Autodesk Fusion 360 part; units mm, degrees
(part 10 of 18)
  line L7212 (85.0332, -136.031) -> (85.0347, -135.871)
  line L7213 (101.229, -141.639) -> (101.57, -141.153)
  line L7214 (169.127, -136.25) -> (169.125, -136.424)
  line L7215 (55.0587, -143.805) -> (54.5607, -144.111)
  line L7216 (155.268, -128.584) -> (155.772, -128.289)
  line L7217 (153.657, -142.493) -> (154.085, -142.905)
  line L7218 (167.879, -140.646) -> (168.153, -140.119)
  line L7219 (58.8266, -133.938) -> (58.9575, -134.508)
  line L7220 (91.5484, -127.659) -> (90.9847, -127.846)
  line L7221 (101.483, -131.217) -> (101.133, -130.737)
  line L7222 (156.578, -144.493) -> (157.132, -144.707)
  line L7223 (103.021, -136.687) -> (103.032, -136.25)
  line L7224 (154.32, -129.267) -> (154.783, -128.91)
  line L7225 (164.044, -144.384) -> (163.511, -144.623)
  line L7226 (107.909, -37.7791) -> (107.683, -38.3285)
  line L7227 (94.483, -127.304) -> (93.8893, -127.297)
  line L7228 (41.1589, -134.71) -> (41.2769, -134.137)
  line L7229 (155.518, -143.958) -> (156.039, -144.243)
  line L7230 (162.963, -144.727) -> (163.518, -144.517)
  line L7231 (155.772, -128.289) -> (156.295, -128.028)
  line L7232 (86.17, -132.046) -> (85.9088, -132.579)
  line L7233 (153.157, -130.566) -> (152.795, -131.037)
  line L7234 (153.351, -142.306) -> (152.975, -141.859)
  line L7235 (59.1268, -136.25) -> (59.1251, -136.424)
  line L7236 (87.2572, -142.054) -> (87.6569, -142.493)
  line L7237 (151.131, -137.619) -> (151.061, -137.039)
  line L7238 (85.0291, -136.455) -> (85.0332, -136.031)
  line L7239 (89.0175, -143.639) -> (89.5183, -143.958)
  line L7240 (168.602, -139.286) -> (168.389, -139.83)
  line L7241 (59.1251, -136.424) -> (59.0951, -137.007)
  line L7242 (151.382, -138.76) -> (151.238, -138.193)
  line L7243 (90.9847, -127.846) -> (90.4345, -128.069)
  line L7244 (85.2321, -134.849) -> (85.1587, -135.438)
  line L7245 (85.0347, -135.871) -> (85.078, -135.288)
  line L7246 (154.187, -143.121) -> (153.756, -142.727)
  line L7247 (166.453, -142.538) -> (166.856, -142.101)
  line L7248 (98.5813, -143.99) -> (99.0844, -143.674)
  line L7249 (97.3734, -127.924) -> (96.8143, -127.724)
  line L7250 (102.953, -135.066) -> (102.855, -134.48)
  line L7251 (165.059, -143.805) -> (164.561, -144.111)
  line L7252 (169.021, -136.687) -> (169.032, -136.25)
  line L7253 (57.3045, -130.804) -> (57.6409, -131.281)
  line L7254 (90.4345, -128.069) -> (89.9003, -128.329)
  line L7255 (152.17, -132.046) -> (151.909, -132.579)
  line L7256 (55.2028, -128.792) -> (55.6734, -129.138)
  line L7257 (152.795, -131.037) -> (152.466, -131.531)
  line L7258 (168.972, -137.279) -> (169.021, -136.687)
  line L7259 (164.059, -144.271) -> (164.581, -143.99)
  line L7260 (55.5358, -143.468) -> (55.0587, -143.805)
  line L7261 (151.078, -135.288) -> (151.159, -134.71)
  line L7262 (167.641, -131.281) -> (167.946, -131.78)
  line L7263 (169.108, -135.666) -> (169.127, -136.25)
  line L7264 (48.9269, -145.227) -> (48.35, -145.134)
  line L7265 (168.885, -137.867) -> (168.972, -137.279)
  line L7266 (156.039, -144.243) -> (156.578, -144.493)
  line L7267 (108.795, -36.2371) -> (108.466, -36.7311)
  line L7268 (153.257, -142.054) -> (153.657, -142.493)
  line L7269 (85.9741, -140.063) -> (86.2446, -140.591)
  line L7270 (45.7724, -128.289) -> (46.2951, -128.028)
  line L7271 (52.4039, -144.996) -> (51.8346, -145.128)
  line L7272 (152.888, -141.589) -> (153.257, -142.054)
  line L7273 (96.8143, -127.724) -> (96.2432, -127.561)
  line L7274 (167.199, -141.834) -> (166.823, -142.282)
  line L7275 (51.2581, -145.223) -> (50.6766, -145.28)
  line L7276 (151.683, -133.129) -> (151.495, -133.692)
  line L7277 (85.1245, -136.031) -> (85.1297, -136.625)
  line L7278 (108.466, -36.7311) -> (108.17, -37.2459)
  line L7279 (102.719, -133.902) -> (102.544, -133.335)
  line L7280 (41.8482, -132.483) -> (42.1085, -131.96)
  line L7281 (103.012, -135.657) -> (102.953, -135.066)
  line L7282 (107.683, -38.3285) -> (107.495, -38.8917)
  line L7283 (164.199, -128.194) -> (164.711, -128.476)
  line L7284 (152.311, -140.898) -> (152.028, -140.387)
  line L7285 (152.975, -141.859) -> (152.627, -141.389)
  line L7286 (166.543, -129.918) -> (166.938, -130.349)
  line L7287 (98.0585, -144.271) -> (98.5813, -143.99)
  line L7288 (102.885, -137.867) -> (102.972, -137.279)
  line L7289 (107.13, -41.825) -> (107.174, -42.4171)
  line L7290 (163.128, -127.73) -> (163.671, -127.944)
  line L7291 (86.5495, -141.101) -> (86.8876, -141.589)
  line L7292 (53.671, -127.944) -> (54.1995, -128.194)
  line L7293 (151.541, -138.958) -> (151.739, -139.517)
  line L7294 (151.232, -134.849) -> (151.159, -135.438)
  line L7295 (151.124, -136.031) -> (151.13, -136.625)
  line L7296 (168.855, -134.48) -> (168.719, -133.902)
  line L7297 (160.483, -127.304) -> (159.889, -127.297)
  line L7298 (151.777, -139.859) -> (151.562, -139.316)
  line L7299 (85.7774, -139.859) -> (85.5618, -139.316)
  line L7300 (161.816, -145.034) -> (162.395, -144.9)
  line L7301 (89.9003, -128.329) -> (89.3845, -128.623)
  line L7302 (168.659, -133.378) -> (168.827, -133.938)
  line L7303 (85.3803, -138.386) -> (85.541, -138.958)
  line L7304 (101.801, -131.718) -> (101.483, -131.217)
  line L7305 (169.032, -136.25) -> (169.012, -135.657)
  line L7306 (85.2578, -137.805) -> (85.3803, -138.386)
  line L7307 (100.453, -142.538) -> (100.856, -142.101)
  line L7308 (151.739, -139.517) -> (151.974, -140.063)
  line L7309 (87.5489, -130.12) -> (87.157, -130.566)
  line L7310 (165.565, -143.326) -> (166.022, -142.947)
  line L7311 (167.57, -141.153) -> (167.879, -140.646)
  line L7312 (151.277, -134.137) -> (151.432, -133.574)
  line L7313 (102.972, -137.279) -> (103.021, -136.687)
  line L7314 (51.4301, -127.302) -> (52.0047, -127.408)
  line L7315 (58.4559, -132.831) -> (58.6591, -133.378)
  line L7316 (55.6734, -129.138) -> (56.1207, -129.514)
  line L7317 (166.753, -130.281) -> (166.342, -129.852)
  line L7318 (154.889, -128.951) -> (154.417, -129.31)
  line L7319 (57.5441, -141.363) -> (57.1986, -141.834)
  line L7320 (85.7392, -139.517) -> (85.9741, -140.063)
  line L7321 (151.035, -135.871) -> (151.078, -135.288)
  line L7322 (157.22, -144.837) -> (156.672, -144.635)
  line L7323 (95.075, -127.351) -> (94.483, -127.304)
  line L7324 (163.511, -144.623) -> (162.963, -144.827)
  line L7325 (54.1995, -128.194) -> (54.7108, -128.476)
  line L7326 (86.6274, -141.389) -> (86.3113, -140.898)
  line L7327 (59.0951, -137.007) -> (59.0274, -137.588)
  line L7328 (99.4411, -129.079) -> (98.954, -128.74)
  line L7329 (151.622, -133.022) -> (151.848, -132.483)
  line L7330 (169.051, -135.084) -> (169.108, -135.666)
  line L7331 (102.391, -139.576) -> (102.594, -139.017)
  line L7332 (159.099, -127.253) -> (159.682, -127.209)
  line L7333 (161.663, -127.437) -> (161.075, -127.351)
  line L7334 (56.1207, -129.514) -> (56.5428, -129.918)
  line L7335 (168.389, -139.83) -> (168.14, -140.359)
  line L7336 (50.8498, -127.233) -> (51.4301, -127.302)
  line L7337 (45.2676, -128.584) -> (45.7724, -128.289)
  line L7338 (53.5109, -144.623) -> (52.9634, -144.827)
  line L7339 (85.1309, -137.619) -> (85.0612, -137.039)
  line L7340 (151.344, -134.266) -> (151.232, -134.849)
  line L7341 (169.027, -137.588) -> (168.922, -138.162)
  line L7342 (163.373, -127.924) -> (162.814, -127.724)
  line L7343 (159.889, -127.297) -> (159.296, -127.329)
  line L7344 (46.8336, -127.801) -> (47.3856, -127.609)
  line L7345 (161.258, -145.223) -> (160.677, -145.28)
  line L7346 (94.6391, -145.187) -> (95.2302, -145.13)
  line L7347 (85.541, -138.958) -> (85.7392, -139.517)
  line L7348 (42.7274, -130.969) -> (43.0836, -130.506)
  line L7349 (88.0847, -142.905) -> (88.539, -143.287)
  line L7350 (107.159, -40.6384) -> (107.124, -41.2312)
  line L7351 (159.682, -127.209) -> (160.266, -127.202)
  line L7352 (55.9903, -143.101) -> (55.5358, -143.468)
  line L7353 (167.133, -130.737) -> (166.753, -130.281)
  line L7354 (85.3817, -138.76) -> (85.2379, -138.193)
  line L7355 (153.97, -129.701) -> (153.549, -130.12)
  line L7356 (41.078, -135.288) -> (41.1589, -134.71)
  line L7357 (155.9, -128.329) -> (155.385, -128.623)
  line L7358 (153.549, -130.12) -> (153.157, -130.566)
  line L7359 (86.0276, -140.387) -> (85.7774, -139.859)
  line L7360 (159.296, -127.329) -> (158.707, -127.4)
  line L7361 (52.0047, -127.408) -> (52.5713, -127.551)
  line L7362 (156.672, -144.635) -> (156.138, -144.398)
  line L7363 (164.711, -128.476) -> (165.203, -128.792)
  line L7364 (154.643, -143.487) -> (154.187, -143.121)
  line L7365 (109.157, -35.766) -> (108.795, -36.2371)
  line L7366 (49.5085, -145.282) -> (48.9269, -145.227)
  line L7367 (101.133, -130.737) -> (100.753, -130.281)
  line L7368 (95.6626, -127.437) -> (95.075, -127.351)
  line L7369 (153.084, -130.506) -> (153.469, -130.066)
  line L7370 (102.084, -132.24) -> (101.801, -131.718)
  line L7371 (165.904, -129.451) -> (165.441, -129.079)
  line L7372 (86.9746, -141.859) -> (86.6274, -141.389)
  line L7373 (168.14, -140.359) -> (167.858, -140.87)
  line L7374 (88.539, -143.287) -> (89.0175, -143.639)
  line L7375 (154.783, -128.91) -> (155.268, -128.584)
  line L7376 (168.084, -132.24) -> (167.801, -131.718)
  line L7377 (164.954, -128.74) -> (164.446, -128.433)
  line L7378 (165.536, -143.468) -> (165.059, -143.805)
  line L7379 (165.441, -129.079) -> (164.954, -128.74)
  line L7380 (50.2663, -127.202) -> (50.8498, -127.233)
  line L7381 (109.97, -34.9007) -> (109.549, -35.3199)
  line L7382 (91.1318, -144.707) -> (91.6987, -144.883)
  line L7383 (152.55, -141.101) -> (152.888, -141.589)
  line L7384 (57.9457, -131.78) -> (58.2178, -132.297)
  line L7385 (58.1404, -140.359) -> (57.8585, -140.87)
  line L7386 (99.5654, -143.326) -> (100.022, -142.947)
  line L7387 (156.138, -144.398) -> (155.62, -144.127)
  line L7388 (96.3945, -144.9) -> (96.9627, -144.727)
  line L7389 (101.879, -140.646) -> (102.153, -140.119)
  line L7390 (158.707, -127.4) -> (158.123, -127.511)
  line L7391 (153.469, -130.066) -> (153.882, -129.653)
  line L7392 (151.159, -134.71) -> (151.277, -134.137)
  line L7393 (151.238, -138.193) -> (151.131, -137.619)
  line L7394 (44.3203, -129.267) -> (44.7829, -128.91)
  line L7395 (164.581, -143.99) -> (165.084, -143.674)
  line L7396 (50.6766, -145.28) -> (50.0926, -145.3)
  line L7397 (85.495, -133.692) -> (85.3443, -134.266)
  line L7398 (43.0836, -130.506) -> (43.4688, -130.066)
  line L7399 (168.153, -140.119) -> (168.391, -139.576)
  line L7400 (52.5713, -127.551) -> (53.1275, -127.73)
  line L7401 (52.9634, -144.827) -> (52.4039, -144.996)
  line L7402 (162.005, -127.408) -> (162.571, -127.551)
  line L7403 (159.509, -145.282) -> (158.927, -145.227)
  line L7404 (162.571, -127.551) -> (163.128, -127.73)
  line L7405 (159.452, -145.183) -> (160.046, -145.205)
  line L7406 (43.4688, -130.066) -> (43.8816, -129.653)
  line L7407 (167.483, -131.217) -> (167.133, -130.737)
  line L7408 (160.639, -145.187) -> (161.23, -145.13)
  line L7409 (93.4521, -145.183) -> (94.0455, -145.205)
  line L7410 (160.85, -127.233) -> (161.43, -127.302)
  line L7411 (87.157, -130.566) -> (86.7955, -131.037)
  line L7412 (168.758, -138.447) -> (168.885, -137.867)
  line L7413 (54.0441, -144.384) -> (53.5109, -144.623)
  line L7414 (99.9045, -129.451) -> (99.4411, -129.079)
  line L7415 (168.456, -132.831) -> (168.659, -133.378)
  line L7416 (166.121, -129.514) -> (166.543, -129.918)
  line L7417 (50.0926, -145.3) -> (49.5085, -145.282)
  line L7418 (157.132, -144.707) -> (157.699, -144.883)
  line L7419 (151.13, -136.625) -> (151.174, -137.217)
  line L7420 (95.2302, -145.13) -> (95.8162, -145.034)
  line L7421 (43.8816, -129.653) -> (44.3203, -129.267)
  line L7422 (56.9379, -130.349) -> (57.3045, -130.804)
  line L7423 (165.673, -129.138) -> (166.121, -129.514)
  line L7424 (161.075, -127.351) -> (160.483, -127.304)
  line L7425 (56.5428, -129.918) -> (56.9379, -130.349)
  line L7426 (56.8234, -142.282) -> (56.42, -142.705)
  line L7427 (167.544, -141.363) -> (167.199, -141.834)
  line L7428 (167.801, -131.718) -> (167.483, -131.217)
  line L7429 (48.35, -145.134) -> (47.7803, -145.004)
  line L7430 (101.57, -141.153) -> (101.879, -140.646)
  line L7431 (168.719, -133.902) -> (168.544, -133.335)
  line L7432 (168.953, -135.066) -> (168.855, -134.48)
  line L7433 (151.033, -136.031) -> (151.035, -135.871)
  line L7434 (166.823, -142.282) -> (166.42, -142.705)
  line L7435 (49.682, -127.209) -> (50.2663, -127.202)
  line L7436 (152.627, -141.389) -> (152.311, -140.898)
  line L7437 (59.1079, -135.666) -> (59.1268, -136.25)
  line L7438 (151.061, -137.039) -> (151.029, -136.455)
  line L7439 (85.1587, -135.438) -> (85.1245, -136.031)
  line L7440 (164.561, -144.111) -> (164.044, -144.384)
  line L7441 (153.756, -142.727) -> (153.351, -142.306)
  line L7442 (158.123, -127.511) -> (157.548, -127.659)
  line L7443 (168.781, -138.729) -> (168.602, -139.286)
  line L7444 (160.677, -145.28) -> (160.093, -145.3)
  line L7445 (167.304, -130.804) -> (167.641, -131.281)
  line L7446 (156.834, -127.801) -> (157.386, -127.609)
  line L7447 (158.927, -145.227) -> (158.35, -145.134)
  line L7448 (157.78, -145.004) -> (157.22, -144.837)
  line L7449 (47.7803, -145.004) -> (47.2202, -144.837)
  line L7450 (46.2951, -128.028) -> (46.8336, -127.801)
  line L7451 (156.434, -128.069) -> (155.9, -128.329)
  line L7452 (157.949, -127.454) -> (158.521, -127.335)
  line L7453 (168.957, -134.508) -> (169.051, -135.084)
  line L7454 (152.108, -131.96) -> (152.402, -131.454)
  line L7455 (167.946, -131.78) -> (168.218, -132.297)
  line L7456 (47.9488, -127.454) -> (48.5208, -127.335)
  line L7457 (151.909, -132.579) -> (151.683, -133.129)
  line L7458 (169.095, -137.007) -> (169.027, -137.588)
  line L7459 (157.548, -127.659) -> (156.985, -127.846)
  line L7460 (102.332, -132.78) -> (102.084, -132.24)
  line L7461 (97.9179, -128.161) -> (97.3734, -127.924)
  line L7462 (157.386, -127.609) -> (157.949, -127.454)
  line L7463 (168.391, -139.576) -> (168.594, -139.017)
  line L7464 (168.218, -132.297) -> (168.456, -132.831)
  line L7465 (156.295, -128.028) -> (156.834, -127.801)
  line L7466 (47.3856, -127.609) -> (47.9488, -127.454)
  line L7467 (125.012, -40.8565) -> (124.953, -40.2656)
  line L7468 (113.548, -32.8593) -> (112.985, -33.0458)
  line L7469 (122.342, -35.0519) -> (121.904, -34.6507)
  line L7470 (119.918, -33.3606) -> (119.373, -33.1239)
  line L7471 (122.753, -35.4812) -> (122.342, -35.0519)
  line L7472 (124.885, -43.0665) -> (124.972, -42.4793)
  line L7473 (120.581, -49.1896) -> (121.084, -48.874)
  line L7474 (122.453, -47.7378) -> (122.856, -47.3014)
  line L7475 (117.075, -32.5508) -> (116.483, -32.5042)
  line L7476 (123.133, -35.9368) -> (122.753, -35.4812)
  line L7477 (111.385, -33.8228) -> (110.889, -34.1505)
  line L7478 (121.565, -48.5258) -> (122.022, -48.1465)
  line L7479 (119.518, -49.7173) -> (120.059, -49.4711)
  line L7480 (125.021, -41.8875) -> (125.032, -41.45)
  line L7481 (116.046, -50.4049) -> (116.639, -50.3873)
  line L7482 (124.544, -38.5345) -> (124.332, -37.9798)
  line L7483 (118.963, -49.9272) -> (119.518, -49.7173)
  line L7484 (118.395, -50.0999) -> (118.963, -49.9272)
  line L7485 (121.441, -34.2794) -> (120.954, -33.9397)
  line L7486 (123.801, -36.9185) -> (123.483, -36.4165)
  line L7487 (116.639, -50.3873) -> (117.23, -50.3304)
  line L7488 (121.904, -34.6507) -> (121.441, -34.2794)
  line L7489 (111.9, -33.5286) -> (111.385, -33.8228)
  line L7490 (119.373, -33.1239) -> (118.814, -32.9237)
  line L7491 (124.953, -40.2656) -> (124.855, -39.68)
  line L7492 (113.132, -49.9069) -> (113.699, -50.0835)
  line L7493 (118.814, -32.9237) -> (118.243, -32.761)
  line L7494 (114.707, -32.6004) -> (114.123, -32.7107)
  line L7495 (114.123, -32.7107) -> (113.548, -32.8593)
  line L7496 (121.084, -48.874) -> (121.565, -48.5258)
  line L7497 (123.879, -45.846) -> (124.153, -45.3193)
  line L7498 (117.663, -32.6365) -> (117.075, -32.5508)
  line L7499 (116.483, -32.5042) -> (115.889, -32.497)
  line L7500 (115.452, -50.3832) -> (116.046, -50.4049)
  line L7501 (124.084, -37.4403) -> (123.801, -36.9185)
  line L7502 (124.972, -42.4793) -> (125.021, -41.8875)
  line L7503 (123.483, -36.4165) -> (123.133, -35.9368)
  line L7504 (120.446, -33.633) -> (119.918, -33.3606)
  line L7505 (115.889, -32.497) -> (115.296, -32.5291)
  line L7506 (122.022, -48.1465) -> (122.453, -47.7378)
  line L7507 (117.23, -50.3304) -> (117.816, -50.2345)
  line L7508 (114.276, -50.2221) -> (114.861, -50.3221)
  line L7509 (124.391, -44.7756) -> (124.594, -44.2172)
  line L7510 (110.889, -34.1505) -> (110.417, -34.5104)
  line L7511 (118.243, -32.761) -> (117.663, -32.6365)
  line L7512 (122.856, -47.3014) -> (123.229, -46.8393)
  line L7513 (124.855, -39.68) -> (124.719, -39.1021)
  line L7514 (112.985, -33.0458) -> (112.434, -33.2692)
  line L7515 (117.816, -50.2345) -> (118.395, -50.0999)
  line L7516 (112.434, -33.2692) -> (111.9, -33.5286)
  line L7517 (124.153, -45.3193) -> (124.391, -44.7756)
  line L7518 (113.699, -50.0835) -> (114.276, -50.2221)
  line L7519 (125.032, -41.45) -> (125.012, -40.8565)
  line L7520 (124.594, -44.2172) -> (124.758, -43.6467)
  line L7521 (123.57, -46.3534) -> (123.879, -45.846)
  line L7522 (115.296, -32.5291) -> (114.707, -32.6004)
  line L7523 (114.861, -50.3221) -> (115.452, -50.3832)
  line L7524 (120.954, -33.9397) -> (120.446, -33.633)
  line L7525 (124.758, -43.6467) -> (124.885, -43.0665)
  line L7526 (124.719, -39.1021) -> (124.544, -38.5345)
  line L7527 (124.332, -37.9798) -> (124.084, -37.4403)
  line L7528 (120.059, -49.4711) -> (120.581, -49.1896)
  line L7529 (123.229, -46.8393) -> (123.57, -46.3534)
  line L7530 (125.095, -42.2073) -> (125.027, -42.7877)
  line L7531 (125.027, -42.7877) -> (124.922, -43.3625)
  line L7532 (107.033, -41.2312) -> (107.035, -41.071)
  line L7533 (112.039, -49.4431) -> (112.578, -49.6931)
  line L7534 (107.238, -43.3934) -> (107.131, -42.8189)
  line L7535 (107.541, -44.1577) -> (107.739, -44.7175)
  line L7536 (107.777, -45.0587) -> (107.562, -44.5156)
  line L7537 (125.127, -41.45) -> (125.125, -41.6237)
  line L7538 (107.562, -44.5156) -> (107.382, -43.9597)
  line L7539 (121.059, -49.0054) -> (120.561, -49.3111)
  line L7540 (124.827, -39.1382) -> (124.957, -39.7077)
  line L7541 (124.14, -45.5586) -> (123.858, -46.0704)
  line L7542 (107.061, -42.2388) -> (107.029, -41.6553)
  line L7543 (124.922, -43.3625) -> (124.781, -43.9293)
  line L7544 (116.677, -50.4801) -> (116.093, -50.5)
  line L7545 (109.756, -47.927) -> (109.351, -47.5056)
  line L7546 (123.858, -46.0704) -> (123.544, -46.563)
  line L7547 (118.963, -50.0273) -> (118.404, -50.1957)
  line L7548 (117.835, -50.3276) -> (117.258, -50.4226)
  line L7549 (115.509, -50.4821) -> (114.927, -50.4266)
  line L7550 (119.511, -49.8231) -> (118.963, -50.0273)
  line L7551 (108.55, -46.301) -> (108.888, -46.7892)
  line L7552 (112.578, -49.6931) -> (113.132, -49.9069)
  line L7553 (107.131, -42.8189) -> (107.061, -42.2388)
  line L7554 (122.823, -47.4821) -> (122.42, -47.9049)
  line L7555 (108.627, -46.589) -> (108.311, -46.0975)
  line L7556 (111.62, -49.3267) -> (111.121, -49.0227)
  line L7557 (108.245, -45.7915) -> (108.55, -46.301)
  line L7558 (108.888, -46.7892) -> (109.257, -47.2539)
  line L7559 (120.044, -49.5841) -> (119.511, -49.8231)
  line L7560 (111.121, -49.0227) -> (110.643, -48.6871)
  line L7561 (109.657, -47.6931) -> (110.085, -48.1049)
  line L7562 (108.028, -45.5867) -> (107.777, -45.0587)
  line L7563 (114.35, -50.3337) -> (113.78, -50.2038)
  line L7564 (110.539, -48.4873) -> (111.018, -48.8389)
  line L7565 (111.018, -48.8389) -> (111.518, -49.1579)
  line L7566 (109.257, -47.2539) -> (109.657, -47.6931)
  line L7567 (124.659, -38.5784) -> (124.827, -39.1382)
  line L7568 (125.108, -40.866) -> (125.127, -41.45)
  line L7569 (124.389, -45.0297) -> (124.14, -45.5586)
  line L7570 (117.258, -50.4226) -> (116.677, -50.4801)
  line L7571 (110.643, -48.6871) -> (110.187, -48.3214)
  line L7572 (116.093, -50.5) -> (115.509, -50.4821)
  line L7573 (108.975, -47.059) -> (108.627, -46.589)
  line L7574 (124.456, -38.0305) -> (124.659, -38.5784)
  line L7575 (124.781, -43.9293) -> (124.602, -44.4858)
  line L7576 (107.035, -41.071) -> (107.078, -40.4883)
  line L7577 (114.927, -50.4266) -> (114.35, -50.3337)
  line L7578 (107.974, -45.2629) -> (108.245, -45.7915)
  line L7579 (111.518, -49.1579) -> (112.039, -49.4431)
  line L7580 (112.138, -49.5979) -> (111.62, -49.3267)
  line L7581 (121.99, -48.3008) -> (121.536, -48.6681)
  line L7582 (124.957, -39.7077) -> (125.051, -40.2844)
  line L7583 (107.739, -44.7175) -> (107.974, -45.2629)
  line L7584 (107.382, -43.9597) -> (107.238, -43.3934)
  line L7585 (109.351, -47.5056) -> (108.975, -47.059)
  line L7586 (123.199, -47.0342) -> (122.823, -47.4821)
  line L7587 (110.187, -48.3214) -> (109.756, -47.927)
  line L7588 (123.544, -46.563) -> (123.199, -47.0342)
  line L7589 (107.174, -42.4171) -> (107.258, -43.005)
  line L7590 (118.404, -50.1957) -> (117.835, -50.3276)
  line L7591 (120.561, -49.3111) -> (120.044, -49.5841)
  line L7592 (108.311, -46.0975) -> (108.028, -45.5867)
  line L7593 (112.672, -49.8351) -> (112.138, -49.5979)
  line L7594 (124.602, -44.4858) -> (124.389, -45.0297)
  line L7595 (113.78, -50.2038) -> (113.22, -50.0373)
  line L7596 (110.085, -48.1049) -> (110.539, -48.4873)
  line L7597 (107.029, -41.6553) -> (107.033, -41.2312)
  line L7598 (125.125, -41.6237) -> (125.095, -42.2073)
  line L7599 (107.258, -43.005) -> (107.38, -43.5861)
  line L7600 (121.536, -48.6681) -> (121.059, -49.0054)
  line L7601 (113.22, -50.0373) -> (112.672, -49.8351)
  line L7602 (122.42, -47.9049) -> (121.99, -48.3008)
  line L7603 (125.051, -40.2844) -> (125.108, -40.866)
  line L7604 (124.218, -37.4969) -> (124.456, -38.0305)
  line L7605 (107.38, -43.5861) -> (107.541, -44.1577)
  line L7606 (173.159, -40.6384) -> (173.124, -41.2312)
  line L7607 (91.3856, -32.8094) -> (91.9488, -32.6538)
  line L7608 (98.5607, -49.3111) -> (98.0441, -49.5841)
  line L7609 (174.466, -36.7311) -> (174.17, -37.2459)
  line L7610 (103.027, -42.7877) -> (102.922, -43.3625)
  line L7611 (89.6204, -49.3267) -> (89.1214, -49.0227)
  line L7612 (92.5208, -32.5348) -> (93.0994, -32.4529)
  line L7613 (85.2769, -39.3373) -> (85.4315, -38.7738)
  line L7614 (93.682, -32.4086) -> (94.2663, -32.402)
  line L7615 (102.14, -45.5586) -> (101.858, -46.0704)
  line L7616 (101.544, -46.563) -> (101.199, -47.0342)
  line L7617 (102.218, -37.4969) -> (102.456, -38.0305)
  line L7618 (101.946, -36.9798) -> (102.218, -37.4969)
  line L7619 (91.7803, -50.2038) -> (91.2202, -50.0373)
  line L7620 (99.2028, -33.9917) -> (99.6734, -34.338)
  line L7621 (101.304, -36.0036) -> (101.641, -36.4813)
  line L7622 (86.1085, -37.1595) -> (86.402, -36.6542)
  line L7623 (96.0047, -32.6077) -> (96.5713, -32.7506)
  line L7624 (86.7274, -36.169) -> (87.0836, -35.7057)
  line L7625 (89.7724, -33.4892) -> (90.2951, -33.228)
  line L7626 (103.095, -42.2073) -> (103.027, -42.7877)
  line L7627 (98.7108, -33.6764) -> (99.2028, -33.9917)
  line L7628 (91.2202, -50.0373) -> (90.672, -49.8351)
  line L7629 (103.108, -40.866) -> (103.127, -41.45)
  line L7630 (95.2581, -50.4226) -> (94.6766, -50.4801)
  line L7631 (95.8346, -50.3276) -> (95.2581, -50.4226)
  line L7632 (102.456, -38.0305) -> (102.659, -38.5784)
  line L7633 (88.7829, -34.1099) -> (89.2676, -33.7835)
  line L7634 (92.35, -50.3337) -> (91.7803, -50.2038)
  line L7635 (85.6222, -38.2215) -> (85.8482, -37.6827)
  line L7636 (94.8498, -32.4331) -> (95.4301, -32.5018)
  line L7637 (102.659, -38.5784) -> (102.827, -39.1382)
  line L7638 (100.823, -47.4821) -> (100.42, -47.9049)
  line L7639 (90.8336, -33.0011) -> (91.3856, -32.8094)
  line L7640 (97.671, -33.1443) -> (98.1995, -33.3936)
  line L7641 (89.1214, -49.0227) -> (88.643, -48.6871)
  line L7642 (98.1995, -33.3936) -> (98.7108, -33.6764)
  line L7643 (88.643, -48.6871) -> (88.1873, -48.3214)
  line L7644 (90.672, -49.8351) -> (90.138, -49.5979)
  line L7645 (94.0926, -50.5) -> (93.5085, -50.4821)
  line L7646 (173.13, -41.825) -> (173.174, -42.4171)
  line L7647 (98.0441, -49.5841) -> (97.5109, -49.8231)
  line L7648 (101.858, -46.0704) -> (101.544, -46.563)
  line L7649 (99.0587, -49.0054) -> (98.5607, -49.3111)
  line L7650 (94.6766, -50.4801) -> (94.0926, -50.5)
  line L7651 (174.17, -37.2459) -> (173.909, -37.7791)
  line L7652 (90.2951, -33.228) -> (90.8336, -33.0011)
  line L7653 (100.121, -34.714) -> (100.543, -35.118)
  line L7654 (100.42, -47.9049) -> (99.9903, -48.3008)
  line L7655 (87.4688, -35.2664) -> (87.8816, -34.8528)
  line L7656 (97.5109, -49.8231) -> (96.9634, -50.0273)
  line L7657 (99.6734, -34.338) -> (100.121, -34.714)
  line L7658 (102.602, -44.4858) -> (102.389, -45.0297)
  line L7659 (85.4315, -38.7738) -> (85.6222, -38.2215)
  line L7660 (173.495, -38.8917) -> (173.344, -39.466)
  line L7661 (102.827, -39.1382) -> (102.957, -39.7077)
  line L7662 (102.389, -45.0297) -> (102.14, -45.5586)
  line L7663 (85.078, -40.4883) -> (85.1589, -39.9096)
  line L7664 (86.402, -36.6542) -> (86.7274, -36.169)
  line L7665 (96.5713, -32.7506) -> (97.1275, -32.9297)
  line L7666 (173.344, -39.466) -> (173.232, -40.0491)
  line L7667 (97.1275, -32.9297) -> (97.671, -33.1443)
  line L7668 (173.124, -41.2312) -> (173.13, -41.825)
  line L7669 (96.9634, -50.0273) -> (96.4039, -50.1957)
  line L7670 (93.5085, -50.4821) -> (92.9269, -50.4266)
  line L7671 (89.2676, -33.7835) -> (89.7724, -33.4892)
  line L7672 (103.051, -40.2844) -> (103.108, -40.866)
  line L7673 (99.9903, -48.3008) -> (99.5358, -48.6681)
  line L7674 (95.4301, -32.5018) -> (96.0047, -32.6077)
  line L7675 (102.781, -43.9293) -> (102.602, -44.4858)
  line L7676 (101.641, -36.4813) -> (101.946, -36.9798)
  line L7677 (102.957, -39.7077) -> (103.051, -40.2844)
  line L7678 (92.9269, -50.4266) -> (92.35, -50.3337)
  line L7679 (103.125, -41.6237) -> (103.095, -42.2073)
  line L7680 (173.683, -38.3285) -> (173.495, -38.8917)
  line L7681 (101.199, -47.0342) -> (100.823, -47.4821)
  line L7682 (85.8482, -37.6827) -> (86.1085, -37.1595)
  line L7683 (99.5358, -48.6681) -> (99.0587, -49.0054)
  line L7684 (87.8816, -34.8528) -> (88.3203, -34.4668)
  line L7685 (103.127, -41.45) -> (103.125, -41.6237)
  line L7686 (87.0836, -35.7057) -> (87.4688, -35.2664)
  line L7687 (93.0994, -32.4529) -> (93.682, -32.4086)
  line L7688 (102.922, -43.3625) -> (102.781, -43.9293)
  line L7689 (91.9488, -32.6538) -> (92.5208, -32.5348)
  line L7690 (88.3203, -34.4668) -> (88.7829, -34.1099)
  line L7691 (173.232, -40.0491) -> (173.159, -40.6384)
  line L7692 (85.1589, -39.9096) -> (85.2769, -39.3373)
  line L7693 (94.2663, -32.402) -> (94.8498, -32.4331)
  line L7694 (100.543, -35.118) -> (100.938, -35.5485)
  line L7695 (96.4039, -50.1957) -> (95.8346, -50.3276)
  line L7696 (173.909, -37.7791) -> (173.683, -38.3285)
  line L7697 (90.138, -49.5979) -> (89.6204, -49.3267)
  line L7698 (100.938, -35.5485) -> (101.304, -36.0036)
  line L7699 (190.972, -42.4793) -> (191.021, -41.8875)
  line L7700 (190.855, -39.68) -> (190.719, -39.1021)
  line L7701 (189.57, -46.3534) -> (189.879, -45.846)
  line L7702 (190.544, -38.5345) -> (190.332, -37.9798)
  line L7703 (177.9, -33.5286) -> (177.385, -33.8228)
  line L7704 (191.012, -40.8565) -> (190.953, -40.2656)
  line L7705 (183.816, -50.2345) -> (184.395, -50.0999)
  line L7706 (173.382, -43.9597) -> (173.238, -43.3934)
  line L7707 (175.97, -200.801) -> (175.549, -201.22)
  line L7708 (178.985, -33.0458) -> (178.434, -33.2692)
  line L7709 (181.452, -50.3832) -> (182.046, -50.4049)
  line L7710 (190.719, -39.1021) -> (190.544, -38.5345)
  line L7711 (182.483, -32.5042) -> (181.889, -32.497)
  line L7712 (173.174, -42.4171) -> (173.258, -43.005)
  line L7713 (173.033, -41.2312) -> (173.035, -41.071)
  line L7714 (183.663, -32.6365) -> (183.075, -32.5508)
  line L7715 (173.13, -207.725) -> (173.174, -208.317)
  line L7716 (190.594, -44.2172) -> (190.758, -43.6467)
  line L7717 (181.296, -32.5291) -> (180.707, -32.6004)
  line L7718 (175.657, -47.6931) -> (176.085, -48.1049)
  line L7719 (178.434, -33.2692) -> (177.9, -33.5286)
  line L7720 (184.814, -32.9237) -> (184.243, -32.761)
  line L7721 (175.157, -201.666) -> (174.795, -202.137)
  line L7722 (173.495, -204.792) -> (173.344, -205.366)
  line L7723 (180.861, -50.3221) -> (181.452, -50.3832)
  line L7724 (183.23, -50.3304) -> (183.816, -50.2345)
  line L7725 (191.032, -41.45) -> (191.012, -40.8565)
  line L7726 (181.889, -32.497) -> (181.296, -32.5291)
  line L7727 (179.548, -32.8593) -> (178.985, -33.0458)
  line L7728 (176.539, -48.4873) -> (177.018, -48.8389)
  line L7729 (187.441, -34.2794) -> (186.954, -33.9397)
  line L7730 (189.133, -35.9368) -> (188.753, -35.4812)
  line L7731 (173.258, -43.005) -> (173.38, -43.5861)
  line L7732 (180.276, -50.2221) -> (180.861, -50.3221)
  line L7733 (174.55, -46.301) -> (174.888, -46.7892)
  line L7734 (182.046, -50.4049) -> (182.639, -50.3873)
  line L7735 (174.888, -46.7892) -> (175.257, -47.2539)
  line L7736 (63.078, -206.388) -> (63.1589, -205.81)
  line L7737 (188.022, -48.1465) -> (188.453, -47.7378)
  line L7738 (177.385, -33.8228) -> (176.889, -34.1505)
  line L7739 (174.795, -202.137) -> (174.466, -202.631)
  line L7740 (173.974, -45.2629) -> (174.245, -45.7915)
  line L7741 (173.124, -207.131) -> (173.13, -207.725)
  line L7742 (179.699, -50.0835) -> (180.276, -50.2221)
  line L7743 (173.344, -205.366) -> (173.232, -205.949)
  line L7744 (189.483, -36.4165) -> (189.133, -35.9368)
  line L7745 (173.131, -42.8189) -> (173.061, -42.2388)
  line L7746 (186.446, -33.633) -> (185.918, -33.3606)
  line L7747 (176.417, -34.5104) -> (175.97, -34.9007)
  line L7748 (173.232, -205.949) -> (173.159, -206.538)
  line L7749 (180.123, -32.7107) -> (179.548, -32.8593)
  line L7750 (173.159, -206.538) -> (173.124, -207.131)
  line L7751 (186.954, -33.9397) -> (186.446, -33.633)
  line L7752 (173.909, -203.679) -> (173.683, -204.229)
  line L7753 (188.856, -47.3014) -> (189.229, -46.8393)
  line L7754 (184.395, -50.0999) -> (184.963, -49.9272)
  line L7755 (185.518, -49.7173) -> (186.059, -49.4711)
  line L7756 (184.963, -49.9272) -> (185.518, -49.7173)
  line L7757 (174.466, -202.631) -> (174.17, -203.146)
  line L7758 (173.035, -41.071) -> (173.078, -40.4883)
  line L7759 (188.753, -35.4812) -> (188.342, -35.0519)
  line L7760 (180.707, -32.6004) -> (180.123, -32.7107)
  line L7761 (191.021, -41.8875) -> (191.032, -41.45)
  line L7762 (190.084, -37.4403) -> (189.801, -36.9185)
  line L7763 (187.565, -48.5258) -> (188.022, -48.1465)
  line L7764 (175.157, -35.766) -> (174.795, -36.2371)
  line L7765 (187.904, -34.6507) -> (187.441, -34.2794)
  line L7766 (185.373, -33.1239) -> (184.814, -32.9237)
  line L7767 (182.639, -50.3873) -> (183.23, -50.3304)
  line L7768 (179.132, -49.9069) -> (179.699, -50.0835)
  line L7769 (173.238, -43.3934) -> (173.131, -42.8189)
  line L7770 (178.578, -49.6931) -> (179.132, -49.9069)
  line L7771 (175.257, -47.2539) -> (175.657, -47.6931)
  line L7772 (190.153, -45.3193) -> (190.391, -44.7756)
  line L7773 (184.243, -32.761) -> (183.663, -32.6365)
  line L7774 (190.953, -40.2656) -> (190.855, -39.68)
  line L7775 (173.029, -41.6553) -> (173.033, -41.2312)
  line L7776 (187.084, -48.874) -> (187.565, -48.5258)
  line L7777 (175.549, -201.22) -> (175.157, -201.666)
  line L7778 (177.518, -49.1579) -> (178.039, -49.4431)
  line L7779 (190.332, -37.9798) -> (190.084, -37.4403)
  line L7780 (190.758, -43.6467) -> (190.885, -43.0665)
  line L7781 (189.879, -45.846) -> (190.153, -45.3193)
  line L7782 (177.018, -48.8389) -> (177.518, -49.1579)
  line L7783 (175.97, -34.9007) -> (175.549, -35.3199)
  line L7784 (173.541, -44.1577) -> (173.739, -44.7175)
  line L7785 (173.683, -204.229) -> (173.495, -204.792)
  line L7786 (173.562, -44.5156) -> (173.382, -43.9597)
  line L7787 (176.889, -34.1505) -> (176.417, -34.5104)
  line L7788 (174.17, -203.146) -> (173.909, -203.679)
  line L7789 (173.739, -44.7175) -> (173.974, -45.2629)
  line L7790 (174.795, -36.2371) -> (174.466, -36.7311)
  line L7791 (186.581, -49.1896) -> (187.084, -48.874)
  line L7792 (173.38, -43.5861) -> (173.541, -44.1577)
  line L7793 (186.059, -49.4711) -> (186.581, -49.1896)
  line L7794 (185.918, -33.3606) -> (185.373, -33.1239)
  line L7795 (176.085, -48.1049) -> (176.539, -48.4873)
  line L7796 (174.245, -45.7915) -> (174.55, -46.301)
  line L7797 (189.229, -46.8393) -> (189.57, -46.3534)
  line L7798 (183.075, -32.5508) -> (182.483, -32.5042)
  line L7799 (188.453, -47.7378) -> (188.856, -47.3014)
  line L7800 (190.885, -43.0665) -> (190.972, -42.4793)
  line L7801 (189.801, -36.9185) -> (189.483, -36.4165)
  line L7802 (175.549, -35.3199) -> (175.157, -35.766)
  line L7803 (178.039, -49.4431) -> (178.578, -49.6931)
  line L7804 (190.391, -44.7756) -> (190.594, -44.2172)
  line L7805 (188.342, -35.0519) -> (187.904, -34.6507)
  line L7806 (173.061, -42.2388) -> (173.029, -41.6553)
  line L7807 (95.4301, -198.402) -> (96.0047, -198.508)
  line L7808 (107.974, -211.163) -> (108.245, -211.691)
  line L7809 (86.5495, -212.201) -> (86.8876, -212.689)
  line L7810 (125.127, -207.35) -> (125.125, -207.524)
  line L7811 (117.835, -216.228) -> (117.258, -216.323)
  line L7812 (88.643, -214.587) -> (88.1873, -214.221)
  line L7813 (85.541, -210.058) -> (85.7392, -210.617)
  line L7814 (124.855, -205.58) -> (124.719, -205.002)
  line L7815 (92.35, -216.234) -> (91.7803, -216.104)
  line L7816 (94.8498, -198.333) -> (95.4301, -198.402)
  line L7817 (94.6766, -216.38) -> (94.0926, -216.4)
  line L7818 (85.1309, -208.719) -> (85.0612, -208.139)
  line L7819 (114.276, -216.122) -> (114.861, -216.222)
  line L7820 (86.7274, -202.069) -> (87.0836, -201.606)
  line L7821 (102.389, -210.93) -> (102.14, -211.459)
  line L7822 (101.199, -212.934) -> (100.823, -213.382)
  line L7823 (123.133, -201.837) -> (122.753, -201.381)
  line L7824 (87.0836, -201.606) -> (87.4688, -201.166)
  line L7825 (112.578, -215.593) -> (113.132, -215.807)
  line L7826 (108.466, -202.631) -> (108.17, -203.146)
  line L7827 (109.97, -200.801) -> (109.549, -201.22)
  line L7828 (120.059, -215.371) -> (120.581, -215.09)
  line L7829 (86.6274, -212.489) -> (86.3113, -211.998)
  line L7830 (117.258, -216.323) -> (116.677, -216.38)
  line L7831 (124.153, -211.219) -> (124.391, -210.676)
  line L7832 (85.0332, -207.131) -> (85.0347, -206.971)
  line L7833 (123.229, -212.739) -> (123.57, -212.253)
  line L7834 (124.391, -210.676) -> (124.594, -210.117)
  line L7835 (108.245, -211.691) -> (108.55, -212.201)
  line L7836 (96.3945, -216) -> (96.9627, -215.827)
  line L7837 (89.2676, -199.684) -> (89.7724, -199.389)
  line L7838 (118.395, -216) -> (118.963, -215.827)
  line L7839 (102.659, -204.478) -> (102.827, -205.038)
  line L7840 (117.23, -216.23) -> (117.816, -216.134)
  line L7841 (102.827, -205.038) -> (102.957, -205.608)
  line L7842 (107.777, -210.959) -> (107.562, -210.416)
  line L7843 (120.446, -199.533) -> (119.918, -199.261)
  line L7844 (97.5109, -215.723) -> (96.9634, -215.927)
  line L7845 (121.99, -214.201) -> (121.536, -214.568)
  line L7846 (125.012, -206.757) -> (124.953, -206.166)
  line L7847 (124.719, -205.002) -> (124.544, -204.435)
  line L7848 (118.963, -215.827) -> (119.518, -215.617)
  line L7849 (125.027, -208.688) -> (124.922, -209.262)
  line L7850 (98.1995, -199.294) -> (98.7108, -199.576)
  line L7851 (96.9634, -215.927) -> (96.4039, -216.096)
  line L7852 (107.739, -210.617) -> (107.974, -211.163)
  line L7853 (97.671, -199.044) -> (98.1995, -199.294)
  line L7854 (107.174, -208.317) -> (107.258, -208.905)
  line L7855 (99.9903, -214.201) -> (99.5358, -214.568)
  line L7856 (103.127, -207.35) -> (103.125, -207.524)
  line L7857 (116.639, -216.287) -> (117.23, -216.23)
  line L7858 (102.957, -205.608) -> (103.051, -206.184)
  line L7859 (103.108, -206.766) -> (103.127, -207.35)
  line L7860 (93.682, -198.309) -> (94.2663, -198.302)
  line L7861 (89.7724, -199.389) -> (90.2951, -199.128)
  line L7862 (111.385, -199.723) -> (110.889, -200.051)
  line L7863 (107.344, -205.366) -> (107.232, -205.949)
  line L7864 (109.657, -213.593) -> (110.085, -214.005)
  line L7865 (103.051, -206.184) -> (103.108, -206.766)
  line L7866 (110.187, -214.221) -> (109.756, -213.827)
  line L7867 (107.562, -210.416) -> (107.382, -209.86)
  line L7868 (117.075, -198.451) -> (116.483, -198.404)
  line L7869 (101.544, -212.463) -> (101.199, -212.934)
  line L7870 (85.9741, -211.163) -> (86.2446, -211.691)
  line L7871 (92.5208, -198.435) -> (93.0994, -198.353)
  line L7872 (87.2572, -213.154) -> (87.6569, -213.593)
  line L7873 (91.2202, -215.937) -> (90.672, -215.735)
  line L7874 (120.954, -199.84) -> (120.446, -199.533)
  line L7875 (107.035, -206.971) -> (107.078, -206.388)
  line L7876 (124.332, -203.88) -> (124.084, -203.34)
  line L7877 (108.975, -212.959) -> (108.627, -212.489)
  line L7878 (124.781, -209.829) -> (124.602, -210.386)
  line L7879 (107.159, -206.538) -> (107.124, -207.131)
  line L7880 (112.672, -215.735) -> (112.138, -215.498)
  line L7881 (100.823, -213.382) -> (100.42, -213.805)
  line L7882 (109.157, -201.666) -> (108.795, -202.137)
  line L7883 (97.1275, -198.83) -> (97.671, -199.044)
  line L7884 (123.57, -212.253) -> (123.879, -211.746)
  line L7885 (107.13, -207.725) -> (107.174, -208.317)
  line L7886 (107.029, -207.555) -> (107.033, -207.131)
  line L7887 (121.084, -214.774) -> (121.565, -214.426)
  line L7888 (90.5778, -215.593) -> (91.1318, -215.807)
  line L7889 (94.2663, -198.302) -> (94.8498, -198.333)
  line L7890 (114.35, -216.234) -> (113.78, -216.104)
  line L7891 (93.4521, -216.283) -> (94.0455, -216.305)
  line L7892 (112.985, -198.946) -> (112.434, -199.169)
  line L7893 (110.417, -200.41) -> (109.97, -200.801)
  line L7894 (107.38, -209.486) -> (107.541, -210.058)
  line L7895 (94.0455, -216.305) -> (94.6391, -216.287)
  line L7896 (107.541, -210.058) -> (107.739, -210.617)
  line L7897 (115.889, -198.397) -> (115.296, -198.429)
  line L7898 (115.296, -198.429) -> (114.707, -198.5)
  line L7899 (100.938, -201.449) -> (101.304, -201.904)
  line L7900 (93.5085, -216.382) -> (92.9269, -216.327)
  line L7901 (109.351, -213.406) -> (108.975, -212.959)
  line L7902 (107.683, -204.229) -> (107.495, -204.792)
  line L7903 (87.7561, -213.827) -> (87.3513, -213.406)
  line L7904 (85.0291, -207.555) -> (85.0332, -207.131)
  line L7905 (113.699, -215.983) -> (114.276, -216.122)
  line L7906 (108.028, -211.487) -> (107.777, -210.959)
  line L7907 (108.627, -212.489) -> (108.311, -211.998)
  line L7908 (107.033, -207.131) -> (107.035, -206.971)
  line L7909 (121.536, -214.568) -> (121.059, -214.905)
  line L7910 (85.2578, -208.905) -> (85.3803, -209.486)
  line L7911 (113.132, -215.807) -> (113.699, -215.983)
  line L7912 (87.6569, -213.593) -> (88.0847, -214.005)
  line L7913 (95.2302, -216.23) -> (95.8162, -216.134)
  line L7914 (98.0441, -215.484) -> (97.5109, -215.723)
  line L7915 (122.856, -213.201) -> (123.229, -212.739)
  line L7916 (120.581, -215.09) -> (121.084, -214.774)
  line L7917 (122.453, -213.638) -> (122.856, -213.201)
  line L7918 (110.889, -200.051) -> (110.417, -200.41)
  line L7919 (101.641, -202.381) -> (101.946, -202.88)
  line L7920 (116.483, -198.404) -> (115.889, -198.397)
  line L7921 (115.509, -216.382) -> (114.927, -216.327)
  line L7922 (85.0347, -206.971) -> (85.078, -206.388)
  line L7923 (125.032, -207.35) -> (125.012, -206.757)
  line L7924 (124.602, -210.386) -> (124.389, -210.93)
  line L7925 (86.2446, -211.691) -> (86.5495, -212.201)
  line L7926 (89.6204, -215.227) -> (89.1214, -214.923)
  line L7927 (122.342, -200.952) -> (121.904, -200.551)
  line L7928 (111.018, -214.739) -> (111.518, -215.058)
  line L7929 (124.953, -206.166) -> (124.855, -205.58)
  line L7930 (96.5713, -198.651) -> (97.1275, -198.83)
  line L7931 (118.404, -216.096) -> (117.835, -216.228)
  line L7932 (107.061, -208.139) -> (107.029, -207.555)
  line L7933 (125.095, -208.107) -> (125.027, -208.688)
  line L7934 (125.021, -207.787) -> (125.032, -207.35)
  line L7935 (102.781, -209.829) -> (102.602, -210.386)
  line L7936 (123.199, -212.934) -> (122.823, -213.382)
  line L7937 (119.918, -199.261) -> (119.373, -199.024)
  line L7938 (101.858, -211.97) -> (101.544, -212.463)
  line L7939 (109.257, -213.154) -> (109.657, -213.593)
  line L7940 (91.6987, -215.983) -> (92.2761, -216.122)
  line L7941 (125.125, -207.524) -> (125.095, -208.107)
  line L7942 (91.1318, -215.807) -> (91.6987, -215.983)
  line L7943 (99.6734, -200.238) -> (100.121, -200.614)
  line L7944 (124.544, -204.435) -> (124.332, -203.88)
  line L7945 (100.42, -213.805) -> (99.9903, -214.201)
  line L7946 (99.0587, -214.905) -> (98.5607, -215.211)
  line L7947 (110.643, -214.587) -> (110.187, -214.221)
  line L7948 (103.095, -208.107) -> (103.027, -208.688)
  line L7949 (114.123, -198.611) -> (113.548, -198.759)
  line L7950 (117.663, -198.537) -> (117.075, -198.451)
  line L7951 (85.2379, -209.293) -> (85.1309, -208.719)
  line L7952 (119.518, -215.617) -> (120.059, -215.371)
  line L7953 (85.7774, -210.959) -> (85.5618, -210.416)
  line L7954 (86.1085, -203.06) -> (86.402, -202.554)
  line L7955 (95.8346, -216.228) -> (95.2581, -216.323)
  line L7956 (102.14, -211.459) -> (101.858, -211.97)
  line L7957 (98.5813, -215.09) -> (99.0844, -214.774)
  line L7958 (109.549, -201.22) -> (109.157, -201.666)
  line L7959 (124.972, -208.379) -> (125.021, -207.787)
  line L7960 (103.027, -208.688) -> (102.922, -209.262)
  line L7961 (99.5358, -214.568) -> (99.0587, -214.905)
  line L7962 (107.495, -204.792) -> (107.344, -205.366)
  line L7963 (85.3803, -209.486) -> (85.541, -210.058)
  line L7964 (99.2028, -199.892) -> (99.6734, -200.238)
  line L7965 (110.085, -214.005) -> (110.539, -214.387)
  line L7966 (124.084, -203.34) -> (123.801, -202.818)
  line L7967 (85.8482, -203.583) -> (86.1085, -203.06)
  line L7968 (118.814, -198.824) -> (118.243, -198.661)
  line L7969 (109.756, -213.827) -> (109.351, -213.406)
  line L7970 (87.8816, -200.753) -> (88.3203, -200.367)
  line L7971 (90.8336, -198.901) -> (91.3856, -198.709)
  line L7972 (112.138, -215.498) -> (111.62, -215.227)
  line L7973 (102.218, -203.397) -> (102.456, -203.931)
  line L7974 (113.548, -198.759) -> (112.985, -198.946)
  line L7975 (124.594, -210.117) -> (124.758, -209.547)
  line L7976 (121.441, -200.179) -> (120.954, -199.84)
  line L7977 (116.093, -216.4) -> (115.509, -216.382)
  line L7978 (92.8615, -216.222) -> (93.4521, -216.283)
  line L7979 (118.243, -198.661) -> (117.663, -198.537)
  line L7980 (95.8162, -216.134) -> (96.3945, -216)
  line L7981 (100.543, -201.018) -> (100.938, -201.449)
  line L7982 (95.2581, -216.323) -> (94.6766, -216.38)
  line L7983 (112.039, -215.343) -> (112.578, -215.593)
  line L7984 (111.62, -215.227) -> (111.121, -214.923)
  line L7985 (122.823, -213.382) -> (122.42, -213.805)
  line L7986 (85.5618, -210.416) -> (85.3817, -209.86)
  line L7987 (88.0847, -214.005) -> (88.539, -214.387)
  line L7988 (121.904, -200.551) -> (121.441, -200.179)
  line L7989 (85.1742, -208.317) -> (85.2578, -208.905)
  line L7990 (121.565, -214.426) -> (122.022, -214.047)
  line L7991 (90.2951, -199.128) -> (90.8336, -198.901)
  line L7992 (90.138, -215.498) -> (89.6204, -215.227)
  line L7993 (103.125, -207.524) -> (103.095, -208.107)
  line L7994 (85.7392, -210.617) -> (85.9741, -211.163)
  line L7995 (85.6222, -204.122) -> (85.8482, -203.583)
  line L7996 (107.238, -209.293) -> (107.131, -208.719)
  line L7997 (107.124, -207.131) -> (107.13, -207.725)
  line L7998 (85.078, -206.388) -> (85.1589, -205.81)
  line L7999 (94.0926, -216.4) -> (93.5085, -216.382)
  line L8000 (96.0047, -198.508) -> (96.5713, -198.651)
  line L8001 (108.17, -203.146) -> (107.909, -203.679)
  line L8002 (107.382, -209.86) -> (107.238, -209.293)
  line L8003 (92.2761, -216.122) -> (92.8615, -216.222)
  line L8004 (115.452, -216.283) -> (116.046, -216.305)
  line L8005 (91.7803, -216.104) -> (91.2202, -215.937)
  line L8006 (85.2769, -205.237) -> (85.4315, -204.674)
  line L8007 (108.55, -212.201) -> (108.888, -212.689)
  line L8008 (116.677, -216.38) -> (116.093, -216.4)
  line L8009 (122.42, -213.805) -> (121.99, -214.201)
  line L8010 (86.0276, -211.487) -> (85.7774, -210.959)
  line L8011 (98.0585, -215.371) -> (98.5813, -215.09)
  line L8012 (119.511, -215.723) -> (118.963, -215.927)
  line L8013 (124.758, -209.547) -> (124.885, -208.967)
  line L8014 (91.9488, -198.554) -> (92.5208, -198.435)
  line L8015 (111.9, -199.429) -> (111.385, -199.723)
  line L8016 (122.022, -214.047) -> (122.453, -213.638)
  line L8017 (120.044, -215.484) -> (119.511, -215.723)
  line L8018 (90.672, -215.735) -> (90.138, -215.498)
  line L8019 (111.518, -215.058) -> (112.039, -215.343)
  line L8020 (112.434, -199.169) -> (111.9, -199.429)
  line L8021 (98.7108, -199.576) -> (99.2028, -199.892)
  line L8022 (101.946, -202.88) -> (102.218, -203.397)
  line L8023 (94.6391, -216.287) -> (95.2302, -216.23)
  line L8024 (111.121, -214.923) -> (110.643, -214.587)
  line L8025 (85.4315, -204.674) -> (85.6222, -204.122)
  line L8026 (124.885, -208.967) -> (124.972, -208.379)
  line L8027 (88.1873, -214.221) -> (87.7561, -213.827)
  line L8028 (124.922, -209.262) -> (124.781, -209.829)
  line L8029 (89.1214, -214.923) -> (88.643, -214.587)
  line L8030 (107.232, -205.949) -> (107.159, -206.538)
  line L8031 (87.3513, -213.406) -> (86.9746, -212.959)
  line L8032 (89.5183, -215.058) -> (90.0392, -215.343)
  line L8033 (114.927, -216.327) -> (114.35, -216.234)
  line L8034 (85.1589, -205.81) -> (85.2769, -205.237)
  line L8035 (123.483, -202.317) -> (123.133, -201.837)
  line L8036 (124.389, -210.93) -> (124.14, -211.459)
  line L8037 (102.456, -203.931) -> (102.659, -204.478)
  line L8038 (117.816, -216.134) -> (118.395, -216)
  line L8039 (99.0844, -214.774) -> (99.5654, -214.426)
  line L8040 (87.4688, -201.166) -> (87.8816, -200.753)
  line L8041 (85.0612, -208.139) -> (85.0291, -207.555)
  line L8042 (107.131, -208.719) -> (107.061, -208.139)
  line L8043 (102.602, -210.386) -> (102.389, -210.93)
  line L8044 (116.046, -216.305) -> (116.639, -216.287)
  line L8045 (124.14, -211.459) -> (123.858, -211.97)
  line L8046 (107.258, -208.905) -> (107.38, -209.486)
  line L8047 (108.795, -202.137) -> (108.466, -202.631)
  line L8048 (86.402, -202.554) -> (86.7274, -202.069)
  line L8049 (114.707, -198.5) -> (114.123, -198.611)
  line L8050 (90.0392, -215.343) -> (90.5778, -215.593)
  line L8051 (110.539, -214.387) -> (111.018, -214.739)
  line L8052 (88.539, -214.387) -> (89.0175, -214.739)
  line L8053 (92.9269, -216.327) -> (92.35, -216.234)
  line L8054 (123.858, -211.97) -> (123.544, -212.463)
  line L8055 (101.304, -201.904) -> (101.641, -202.381)
  line L8056 (119.373, -199.024) -> (118.814, -198.824)
  line L8057 (86.3113, -211.998) -> (86.0276, -211.487)
  line L8058 (102.922, -209.262) -> (102.781, -209.829)
  line L8059 (120.561, -215.211) -> (120.044, -215.484)
  line L8060 (113.22, -215.937) -> (112.672, -215.735)
  line L8061 (91.3856, -198.709) -> (91.9488, -198.554)
  line L8062 (108.311, -211.998) -> (108.028, -211.487)
  line L8063 (113.78, -216.104) -> (113.22, -215.937)
  line L8064 (86.9746, -212.959) -> (86.6274, -212.489)
  line L8065 (100.121, -200.614) -> (100.543, -201.018)
  line L8066 (93.0994, -198.353) -> (93.682, -198.309)
  line L8067 (121.059, -214.905) -> (120.561, -215.211)
  line L8068 (88.7829, -200.01) -> (89.2676, -199.684)
  line L8069 (98.5607, -215.211) -> (98.0441, -215.484)
  line L8070 (86.8876, -212.689) -> (87.2572, -213.154)
  line L8071 (114.861, -216.222) -> (115.452, -216.283)
  line L8072 (123.879, -211.746) -> (124.153, -211.219)
  line L8073 (88.3203, -200.367) -> (88.7829, -200.01)
  line L8074 (96.4039, -216.096) -> (95.8346, -216.228)
  line L8075 (107.909, -203.679) -> (107.683, -204.229)
  line L8076 (96.9627, -215.827) -> (97.5182, -215.617)
  line L8077 (85.3817, -209.86) -> (85.2379, -209.293)
  line L8078 (108.888, -212.689) -> (109.257, -213.154)
  line L8079 (122.753, -201.381) -> (122.342, -200.952)
  line L8080 (123.801, -202.818) -> (123.483, -202.317)
  line L8081 (118.963, -215.927) -> (118.404, -216.096)
  line L8082 (123.544, -212.463) -> (123.199, -212.934)
  line L8083 (97.5182, -215.617) -> (98.0585, -215.371)
  line L8084 (89.0175, -214.739) -> (89.5183, -215.058)
  line L8085 (190.922, -209.262) -> (190.781, -209.829)
  line L8086 (190.602, -210.386) -> (190.389, -210.93)
  line L8087 (184.963, -215.827) -> (185.518, -215.617)
  line L8088 (96.2432, -198.661) -> (95.6626, -198.537)
  line L8089 (190.544, -204.435) -> (190.332, -203.88)
  line L8090 (85.495, -204.792) -> (85.3443, -205.366)
  line L8091 (85.3443, -205.366) -> (85.2321, -205.949)
  line L8092 (178.295, -199.128) -> (178.834, -198.901)
  line L8093 (190.957, -205.608) -> (191.051, -206.184)
  line L8094 (87.157, -201.666) -> (86.7955, -202.137)
  line L8095 (85.1297, -207.725) -> (85.1742, -208.317)
  line L8096 (191.032, -207.35) -> (191.012, -206.757)
  line L8097 (173.974, -211.163) -> (174.245, -211.691)
  line L8098 (187.565, -214.426) -> (188.022, -214.047)
  line L8099 (100.022, -214.047) -> (100.453, -213.638)
  line L8100 (177.518, -215.058) -> (178.039, -215.343)
  line L8101 (188.453, -213.638) -> (188.856, -213.201)
  line L8102 (189.801, -202.818) -> (189.483, -202.317)
  line L8103 (182.046, -216.305) -> (182.639, -216.287)
  line L8104 (189.57, -212.253) -> (189.879, -211.746)
  line L8105 (102.332, -203.88) -> (102.084, -203.34)
  line L8106 (190.332, -203.88) -> (190.084, -203.34)
  line L8107 (100.453, -213.638) -> (100.856, -213.201)
  line L8108 (178.578, -215.593) -> (179.132, -215.807)
  line L8109 (175.351, -213.406) -> (174.975, -212.959)
  line L8110 (186.581, -215.09) -> (187.084, -214.774)